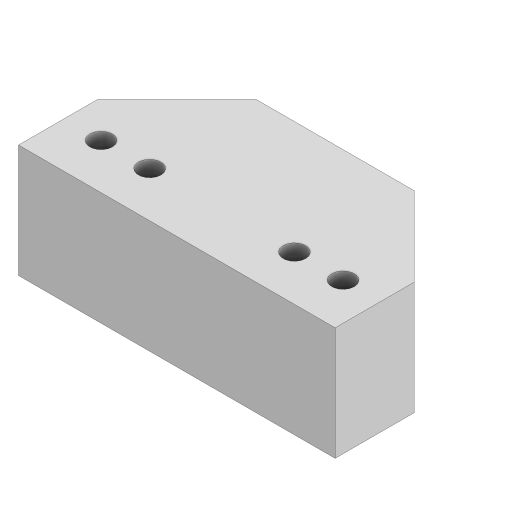
# Autodesk Inventor part: enkoder
Saved by Autodesk Inventor 2025.2 (Build 292293000, 293)
## iProperties
Created: 2025-04-07
Part Number: enkoder
Material: Ogólny
Document SubType Name: Modeling
Designer: Jan Bołtralik
Density: 1 g/cm^3
Appearance: Domyślna
Author: Jan Bołtralik
Autodesk Inventor part; units mm, degrees
ref_plane "YZ Plane" through (0, 0, 0) normal (1, 0, 0) x (0, 1, 0)
ref_plane "XZ Plane" through (0, 0, 0) normal (0, 1, 0) x (-1, 0, 0)
ref_plane "XY Plane" through (0, 0, 0) normal (0, 0, 1) x (1, 0, 0)
sketch "Szkic1" plane through (0, 0, 0) normal (0, 1, 0) x (-1, 0, 0)
  line L0 (0, 0) -> (28, 0)
  line L1 (28, 0) -> (28, -7)
  line L2 (0, 0) -> (0, -7)
  line L3 (28, -7) -> (21, -14)
  line L4 (28, -7) -> (37.8995, -7) construction
  line L5 (0, -7) -> (7, -14)
  line L6 (0, -7) -> (9.8995, -7) construction
  line L7 (7, -14) -> (21, -14)
  line L8 (28, -4) -> (0, -4) construction
  line L9 (14, 0) -> (14, -14) construction
  circle A0 centre (24.7, -4) radius 1
  circle A1 centre (20.4, -4) radius 1
  circle A2 centre (7.6, -4) radius 1
  circle A3 centre (3.3, -4) radius 1
  dimension "d0" = 28
  dimension "d1" = 7
  dimension "d3" = 135
  dimension "d4" = 45
  dimension "d5" = 4
  dimension "d6" = 3.3
  dimension "d7" = 7.6
  dimension "d8" = 2
  dimension "d9" = 2
  dimension "d10" = 2
  dimension "d11" = 2
  constraints: 20 end point, 4 centre point, 4 coincident, 4 horizontal, 4 point on line, 2 equal length, 2 midpoint, 2 perpendicular, 2 symmetric about line, 1 vertical
  measures "d0" distance of L0.start L0.end
  measures "d1" distance of L0.end L1.end
  measures "d3" angle of L3 L4
  measures "d4" angle of L5 L6
  measures "d5" distance between parallel lines of L0 L8
  measures "d6" distance from line of L1 point (24.7, -4)
  measures "d7" distance from line of point (20.4, -4) L1
  measures "d8" diameter of A0
  measures "d9" diameter of A1
  measures "d10" diameter of A2
  measures "d11" diameter of A3
extrude "Wyciągnięcie proste1" add sketch "Szkic1" along normal blind 10
sketch "Szkic2" plane through (-7, 0, -14) normal (0, 0, -1) x (-1, 0, 0)
  line L0 (-7, 0) -> (-7, 10) projected
  line L1 (21, 0) -> (21, 10) projected
  line L2 (0, 10) -> (14, 10) projected
  line L3 (0, 0) -> (14, 0) projected
  line L4 (-7, 4.4) -> (21, 4.4)
  line L5 (21, 2.9) -> (-7, 2.9)
  dimension "d14" = 5.6
  dimension "d15" = 1.5
  constraints: 4 end point, 4 point on line, 2 perpendicular
  measures "d14" distance between parallel lines of L4 L2
  measures "d15" distance between parallel lines of L5 L4
extrude "Wyciągnięcie proste2" cut sketch "Szkic2" against normal up to surface (7 mm away)
